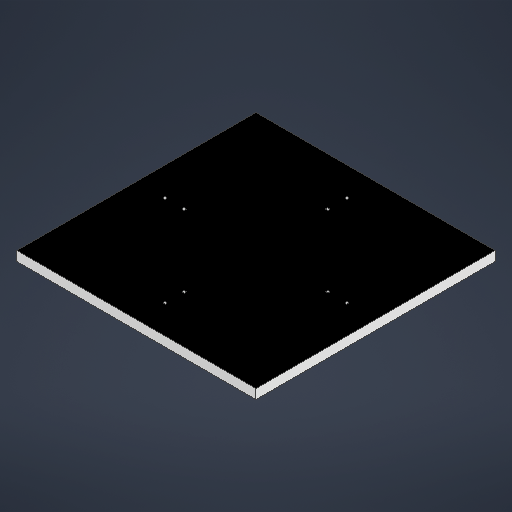
# Autodesk Inventor part: Base plate
Saved by Autodesk Inventor 2026.2 (Build 302298010, 298A)
## iProperties
Created: 2026-10-03
Part Number: Base plate
Material: PVC, hart
Document SubType Name: Modeling
Designer: denis
Mass: 6444.16 g
Surface Area: 5425.64 cm^2
Volume: 4995.48 cm^3
Density: 1.29 g/cm^3
Appearance: Glatt - Weiß
Author: denis
Autodesk Inventor part; units mm, degrees
ref_plane "YZ Plane" through (0, 0, 0) normal (1, 0, 0) x (0, 1, 0)
ref_plane "XZ Plane" through (0, 0, 0) normal (0, 1, 0) x (-1, 0, 0)
ref_plane "XY Plane" through (0, 0, 0) normal (0, 0, 1) x (1, 0, 0)
sketch "Skizze1" plane through (0, 0, 0) normal (0, 0, 1) x (1, 0, 0)
  point P0 (0, 0)
sketch "Skizze2" plane through (0, 0, 0) normal (0, 1, 0) x (-1, 0, 0)
  line L0 (250, 250) -> (-250, 250)
  line L1 (-250, 250) -> (-250, -250)
  line L2 (-250, -250) -> (250, -250)
  line L3 (250, -250) -> (250, 250)
  line L4 (0, -350) -> (0, 350) construction
  line L5 (350, 0) -> (-350, 0) construction
  point P0 (0, 0)
  dimension "d0" = 500
  dimension "d1" = 500
  constraints: 8 end point, 2 parallel, 1 horizontal, 1 perpendicular, 2 other
  measures "d0" distance of L2.end L1.end
  measures "d1" distance of L1.end L0.end
extrude "Extrusion1" add sketch "Skizze2" along normal mid plane 20
sketch "Skizze4" plane through (0, 10, 0) normal (0, 1, 0) x (1, 0, 0)
  line L0 (-250, 250) -> (-250, -250) construction
  line L1 (250, 250) -> (-250, 250) construction
  point P0 (0, 0)
  point P1 (-190, 0)
  dimension "d4" = 60
  dimension "d12" = 250
  measures "d4" distance from line of L0 point (-190, 0)
  measures "d12" distance from line of L1 point (-190, 0)
hole "Bohrung1" at (-190, 10, 0) direction (0, -1, 0) diameter 6 end through all
sketch "Skizze5" plane through (0, 10, 0) normal (0, 1, 0) x (1, 0, 0)
  line L0 (-250, 250) -> (-250, -250) construction
  line L1 (250, 250) -> (-250, 250) construction
  point P0 (0, 0)
  point P1 (-150, 0)
  dimension "d13" = 100
  dimension "d14" = 250
  measures "d13" distance from line of L0 point (-150, 0)
  measures "d14" distance from line of L1 point (-150, 0)
hole "Bohrung2" at (-150, 10, 0) direction (0, -1, 0) diameter 6 end through all
sketch "Skizze6" plane through (0, 10, 0) normal (0, 1, 0) x (1, 0, 0)
  line L0 (250, 250) -> (-250, 250) construction
  line L1 (250, -250) -> (250, 250) construction
  point P0 (0, 0)
  point P1 (190, 0)
  dimension "d22" = 250
  dimension "d30" = 60
  measures "d22" distance from line of L0 point (190, 0)
  measures "d30" distance from line of L1 point (190, 0)
hole "Bohrung3" at (190, 10, 0) direction (0, -1, 0) diameter 6 end through all
sketch "Skizze7" plane through (0, 10, 0) normal (0, 1, 0) x (1, 0, 0)
  line L0 (250, 250) -> (-250, 250) construction
  line L1 (250, -250) -> (250, 250) construction
  point P0 (0, 0)
  point P1 (150, 0)
  dimension "d31" = 250
  dimension "d39" = 100
  measures "d31" distance from line of L0 point (150, 0)
  measures "d39" distance from line of L1 point (150, 0)
hole "Bohrung4" at (150, 10, 0) direction (0, -1, 0) diameter 6 end through all
sketch "Skizze8" plane through (0, 10, 0) normal (0, 1, 0) x (1, 0, 0)
  line L0 (-250, -250) -> (250, -250) construction
  line L1 (250, -250) -> (250, 250) construction
  line L2 (250, 250) -> (-250, 250) construction
  point P0 (0, 0)
  point P1 (0, 190)
  point P2 (0, 150)
  point P3 (0, -150)
  point P4 (0, -190)
  dimension "d40" = 60
  dimension "d41" = 250
  dimension "d42" = 100
  dimension "d43" = 250
  dimension "d44" = 100
  dimension "d45" = 250
  dimension "d46" = 250
  dimension "d47" = 60
  measures "d40" distance from line of L0 point (0, -190)
  measures "d41" distance from line of L1 point (0, -190)
  measures "d42" distance from line of L0 point (0, -150)
  measures "d43" distance from line of L1 point (0, -150)
  measures "d44" distance from line of L2 point (0, 150)
  measures "d45" distance from line of L1 point (0, 150)
  measures "d46" distance from line of L1 point (0, 190)
  measures "d47" distance from line of L2 point (0, 190)
hole "Bohrung5" at (0, 10, 190) at (0, 10, 150) at (0, 10, -150) at (0, 10, -190) direction (0, -1, 0) diameter 6 end through all
